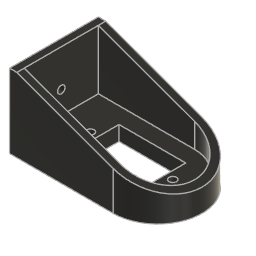
Wrist (Autodesk Fusion 360 design; units mm, degrees)
Autodesk Fusion 360 part; units mm, degrees
sketch "Sketch1" plane through (0, 0, 0) normal (0, 0, 1) x (1, 0, 0)
  line L0 (0, 0) -> (35, 0)
  line L1 (35, -30) -> (0, -30)
  line L2 (0, -30) -> (0, 0)
  arc A0 (35, -30) -> (35, 0) centre (35, -15) ccw
  arc A1 (35, -27.5) -> (35, -2.5) centre (35, -15) ccw
  line L3 (2.5, -2.5) -> (35, -2.5)
  line L4 (2.5, -27.5) -> (2.5, -2.5)
  line L5 (35, -27.5) -> (2.5, -27.5)
  dimension "d183" = 30
  dimension "d185" = 2.5
  constraint horizontal L0
  constraint horizontal L1
  constraint vertical L2
  constraint coincident L0.start L2.end
  constraint tangent L1 A0
  measures "d183" distance of L0.start L1.end
extrude "Extrude1" add sketch "Sketch1" along normal blind 25
extrude "Extrude2" add sketch "Sketch1" along normal blind 5 contours A1 L3 L4 L5
sketch "Sketch2" plane through (0, 0, 5) normal (0, 0, 1) x (-1, 0, 0)
  arc A0 (-35, 27.5) -> (-35, 2.5) centre (-35, 15) ccw
  line L0 (-35, 2.5) -> (-2.5, 2.5)
  line L1 (-2.5, 2.5) -> (-2.5, 27.5)
  line L2 (-2.5, 27.5) -> (-35, 27.5)
  line L3 (-14.9601, 8) -> (-37.4601, 8)
  line L4 (-37.4601, 8) -> (-37.4601, 22)
  line L5 (-37.4601, 22) -> (-14.9601, 22)
  line L6 (-14.9601, 22) -> (-14.9601, 8)
  line L7 (-2.5, 2.5) -> (-35, 2.5)
  circle A1 centre (-40.1101, 15) radius 1.5
  line L8 (-26.2101, 7.8307) -> (-26.2101, 11.6731) construction
  circle A2 centre (-12.3101, 15) radius 1.5
  dimension "d190" = 22.5
  dimension "d191" = 14
  dimension "d192" = 5.5
  dimension "d193" = 3
  dimension "d196" = 7
  dimension "d249" = 2.65
  constraint horizontal L3
  constraint vertical L4
  constraint horizontal L5
  constraint vertical L6
  constraint perpendicular L3 L8
  constraint symmetric A1 L8 A2
  measures "d190" distance of L3.start L3.end
  measures "d191" distance of L3.start L5.end
  measures "d192" distance of L3 L7
  measures "d193" diameter of A1
  measures "d196" distance of L3 A1.centre
  measures "d249" distance of L4 A1.centre
extrude "Extrude3" cut sketch "Sketch2" against normal blind 5 contours L3 L4 L5 L6
extrude "Extrude4" cut sketch "Sketch2" against normal blind 3 contours A1 | A2
thread "Thread1" "ISO Metric profile 3.0 M3x0.5 M3x0.5 6H" major diameter 3.086 minor diameter 2.529 pitch 0.5 angle 60 resizes the face on face at (10.812, -14.9252, 3) on face at (39.7039, -13.5561, 4)
ref_plane "WorkPlane1" through (2.5, -15, 25) normal (0.34202, 0, 0.939693) x (0, 1, 0)
sketch "Sketch3" plane through (8.3273, 0, 22.879) normal (0.34202, 0, 0.939693) x (0, 1, 0)
  line L0 (4.2795, -53.7023) -> (-35.7205, -53.7023)
  line L1 (-35.7205, -53.7023) -> (-35.7205, 66.2977)
  line L2 (-35.7205, 66.2977) -> (4.2795, 66.2977)
  line L3 (4.2795, 66.2977) -> (4.2795, -53.7023)
  line L4 (4.2795, -53.7023) -> (-35.7205, 66.2977) construction
  line L5 (-35.7205, -53.7023) -> (4.2795, 66.2977) construction
  point P0 (-15.7205, 6.2977)
  dimension "d205" = 40
  dimension "d206" = 120
  constraint horizontal L0
  constraint perpendicular L0 L1
  constraint parallel L0 L2
  constraint parallel L1 L3
  constraint coincident L4 P0
  constraint coincident L5 P0
  measures "d205" distance of L1.end L2.end
  measures "d206" distance of L0.end L1.end
extrude "Extrude5" cut sketch "Sketch3" along normal blind 30
sketch "Sketch4" plane through (0, 0, 0) normal (-1, 0, 0) x (0, -1, 0)
  line L0 (0, 0) -> (30, 0)
  line L1 (30, 0) -> (30, 25)
  line L2 (30, 25) -> (0, 25)
  line L3 (0, 25) -> (0, 0)
  circle A0 centre (15, 12.5) radius 1.5
  dimension "d209" = 3
  measures "d209" diameter of A0
extrude "Extrude6" cut sketch "Sketch4" against normal blind 10 contours A0
thread "Thread2" "ISO Metric profile 3.0 M3x0.5 M3x0.5 6H" major diameter 3.086 minor diameter 2.529 pitch 0.5 angle 60 resizes the face on face at (0.8333, -16.4925, 12.3506)
